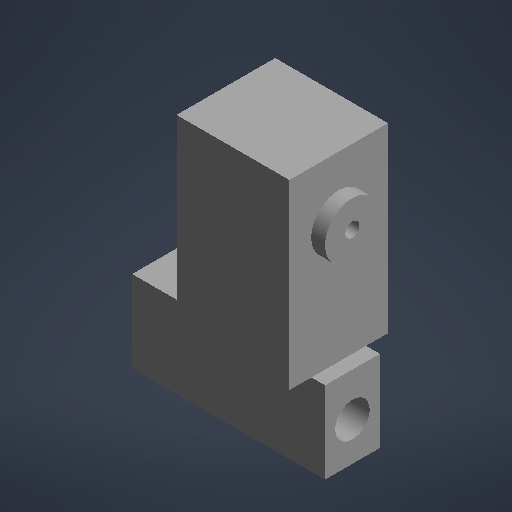
# Autodesk Inventor part: R2_muslo_izq
Saved by Autodesk Inventor 2027 (Build 310192060, 192F)
## iProperties
Part Number: R2_muslo_izq
Material: Genérico
Document SubType Name: Modelado
Designer: rodri
Appearance: Por defecto
Author: rodri
Autodesk Inventor part; units mm, degrees
ref_plane "Plano de trabajo1" through (0, 0, -16.5) normal (0, 0, 1) x (1, 0, 0)
sketch "Boceto1" plane through (0, 0, -16.5) normal (0, 0, 1) x (1, 0, 0)
  line L0 (26.9, -70.1) -> (47.5, -70.1)
  line L1 (47.5, -70.1) -> (47.5, -36.9)
  line L2 (47.5, -36.9) -> (26.9, -36.9)
  line L3 (26.9, -36.9) -> (26.9, -70.1)
  constraints: 8 end point, 2 parallel, 1 horizontal, 1 perpendicular
extrude "Extrusión1" add sketch "Boceto1" along normal blind 18
ref_plane "Plano de trabajo2" through (0, 0, -14) normal (0, 0, 1) x (1, 0, 0)
sketch "Boceto2" plane through (0, 0, -14) normal (0, 0, 1) x (1, 0, 0)
  line L0 (26.8, -65.3) -> (45, -65.3)
  line L1 (45, -65.3) -> (45, -41.7)
  line L2 (45, -41.7) -> (26.8, -41.7)
  line L3 (26.8, -41.7) -> (26.8, -65.3)
  constraints: 8 end point, 2 parallel, 1 horizontal, 1 perpendicular
extrude "Extrusión2" cut sketch "Boceto2" along normal blind 13
ref_plane "Plano de trabajo3" through (0, 0, -11) normal (0, 0, 1) x (1, 0, 0)
sketch "Boceto3" plane through (0, 0, -11) normal (0, 0, 1) x (1, 0, 0)
  line L0 (40, -70.5) -> (45, -70.5)
  line L1 (45, -70.5) -> (45, -63.5)
  line L2 (45, -63.5) -> (40, -63.5)
  line L3 (40, -63.5) -> (40, -70.5)
  constraints: 8 end point, 2 parallel, 1 horizontal, 1 perpendicular
extrude "Extrusión3" cut sketch "Boceto3" along normal blind 7
ref_plane "Plano de trabajo4" through (26.8, 0, 0) normal (1, 0, 0) x (0, 1, 0)
sketch "Boceto4" plane through (26.8, 0, 0) normal (1, 0, 0) x (0, 1, 0)
  circle A0 centre (-67.4, -7.5) radius 0.85
  constraints: 1 centre point
extrude "Extrusión4" cut sketch "Boceto4" along normal blind 6.1
ref_plane "Plano de trabajo5" through (26.8, 0, 0) normal (1, 0, 0) x (0, 1, 0)
sketch "Boceto5" plane through (26.8, 0, 0) normal (1, 0, 0) x (0, 1, 0)
  circle A0 centre (-39.6, -7.5) radius 0.85
  constraints: 1 centre point
extrude "Extrusión5" cut sketch "Boceto5" along normal blind 6.1
ref_plane "Plano de trabajo6" through (47.49, 0, 0) normal (1, 0, 0) x (0, 1, 0)
sketch "Boceto6" plane through (47.49, 0, 0) normal (1, 0, 0) x (0, 1, 0)
  circle A0 centre (-48, -7.5) radius 5
  constraints: 1 centre point
extrude "Extrusión6" add sketch "Boceto6" along normal blind 2.51
ref_plane "Plano de trabajo7" through (45.6, 0, 0) normal (1, 0, 0) x (0, 1, 0)
sketch "Boceto7" plane through (45.6, 0, 0) normal (1, 0, 0) x (0, 1, 0)
  circle A0 centre (-48, -7.5) radius 1.3
  constraints: 1 centre point
extrude "Extrusión7" cut sketch "Boceto7" along normal blind 4.5
ref_plane "Plano de trabajo8" through (0, 0, -12.5) normal (0, 0, 1) x (1, 0, 0)
sketch "Boceto8" plane through (0, 0, -12.5) normal (0, 0, 1) x (1, 0, 0)
  line L0 (14.8, -85) -> (50, -85)
  line L1 (50, -85) -> (50, -70.1)
  line L2 (50, -70.1) -> (14.8, -70.1)
  line L3 (14.8, -70.1) -> (14.8, -85)
  constraints: 8 end point, 2 parallel, 1 horizontal, 1 perpendicular
extrude "Extrusión8" add sketch "Boceto8" along normal blind 10
ref_plane "Plano de trabajo9" through (14.7, 0, 0) normal (1, 0, 0) x (0, 1, 0)
sketch "Boceto9" plane through (14.7, 0, 0) normal (1, 0, 0) x (0, 1, 0)
  circle A0 centre (-78, -7.5) radius 3.15
  constraints: 1 centre point
extrude "Extrusión9" cut sketch "Boceto9" along normal blind 35.4
